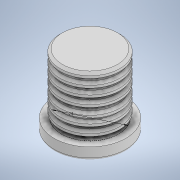
# Autodesk Inventor part: dop_teava_30_ext_24_int
Saved by Autodesk Inventor 2022.6 (Build 266554000, 554)
## iProperties
Created: 2026-07-30
Part Number: dop_teava_30_ext_24_int
Material: Generic
Document SubType Name: Modeling
Designer: Dragos Macovei
Density: 1 g/cm^3
Appearance: Default
Author: Dragos Macovei
Autodesk Inventor part; units mm, degrees
ref_plane "YZ Plane" through (0, 0, 0) normal (1, 0, 0) x (0, 1, 0)
ref_plane "XZ Plane" through (0, 0, 0) normal (0, 1, 0) x (-1, 0, 0)
ref_plane "XY Plane" through (0, 0, 0) normal (0, 0, 1) x (1, 0, 0)
sketch "Sketch1" plane through (0, 0, 0) normal (0, 1, 0) x (-1, 0, 0)
  circle A0 centre (0, 0) radius 15
  dimension "d0" = 30
  constraints: 1 centre point, 1 coincident
  measures "d0" diameter of A0
extrude "Extrusion1" add sketch "Sketch1" along normal blind 5
sketch "Sketch2" plane through (0, 5, 0) normal (0, 1, 0) x (1, 0, 0)
  circle A0 centre (0, 0) radius 7
  dimension "d3" = 14
  constraints: 1 centre point, 1 coincident
  measures "d3" diameter of A0
extrude "Extrusion2" add sketch "Sketch2" along normal blind 25
sketch "Sketch3" plane through (0, 5, 0) normal (0, 1, 0) x (1, 0, 0)
  circle A0 centre (0, 0) radius 12 construction
  dimension "d6" = 24
  constraints: 1 centre point, 1 coincident
  measures "d6" diameter of A0
sketch "Sketch4" plane through (0, 0, 0) normal (0, 0, 1) x (1, 0, 0)
  line L0 (7, 30) -> (-7, 30) projected
  line L1 (7, 30) -> (-7, 30) projected
  line L2 (0, 30) -> (0, 19.913) construction
  line L3 (7, 5) -> (7, 30) projected
  line L4 (7, 30) -> (11.5, 30)
  line L5 (12.5, 29) -> (12.5, 28)
  line L6 (12.5, 28) -> (7, 28)
  line L7 (7, 28) -> (7, 30)
  line L8 (7, 26.5) -> (11.5, 26.5)
  line L9 (12.5, 25.5) -> (12.5, 24.5)
  line L10 (12.5, 24.5) -> (7, 24.5)
  line L11 (7, 24.5) -> (7, 26.5)
  line L12 (7, 23) -> (11.5, 23)
  line L13 (12.5, 22) -> (12.5, 21)
  line L14 (12.5, 21) -> (7, 21)
  line L15 (7, 21) -> (7, 23)
  line L16 (7, 19.5) -> (11.5, 19.5)
  line L17 (12.5, 18.5) -> (12.5, 17.5)
  line L18 (12.5, 17.5) -> (7, 17.5)
  line L19 (7, 17.5) -> (7, 19.5)
  line L20 (11.5, 30) -> (12.5, 29)
  line L21 (11.5, 26.5) -> (12.5, 25.5)
  line L22 (11.5, 23) -> (12.5, 22)
  line L23 (11.5, 19.5) -> (12.5, 18.5)
  line L24 (7, 5) -> (7, 30) projected
  line L25 (7, 7) -> (12.5, 7)
  line L26 (12.5, 7) -> (12.5, 8)
  line L27 (11.5, 9) -> (7, 9)
  line L28 (7, 9) -> (7, 7)
  line L29 (10, 5) -> (10, 30) projected
  line L30 (10, 5) -> (10, 30) projected
  line L31 (11.5, 9) -> (12.5, 8)
  line L32 (7, 5) -> (7, 30) projected
  line L33 (7, 10.5) -> (12.5, 10.5)
  line L34 (12.5, 10.5) -> (12.5, 11.5)
  line L35 (11.5, 12.5) -> (7, 12.5)
  line L36 (7, 12.5) -> (7, 10.5)
  line L37 (7, 5) -> (7, 30) projected
  line L38 (7, 13.6464) -> (12.5, 13.6464)
  line L39 (12.5, 13.6464) -> (12.5, 14.6464)
  line L40 (11.5, 15.6464) -> (7, 15.6464)
  line L41 (7, 15.6464) -> (7, 13.6464)
  line L42 (12.5, 11.5) -> (11.5, 12.5)
  line L43 (12.5, 14.6464) -> (11.5, 15.6464)
  point P0 (0, 0)
  point P1 (-7, 6.5)
  point P2 (7, 6.5)
  point P3 (12.5, 30)
  point P4 (12.5, 26.5)
  point P5 (12.5, 23)
  point P6 (12.5, 19.5)
  point P7 (9.75, 28)
  point P8 (7, 17.5)
  point P9 (7, 21)
  point P10 (7, 24.5)
  point P11 (7, 28)
  point P12 (12.5, 9)
  point P13 (12.5, 12.5)
  point P14 (12.5, 15.6464)
  dimension "d8" = 5.5
  dimension "d9" = 2
  dimension "d10" = 5.5
  dimension "d11" = 2
  dimension "d12" = 5.5
  dimension "d13" = 2
  dimension "d14" = 5.5
  dimension "d15" = 2
  dimension "d16" = 1.5
  dimension "d17" = 1.5
  dimension "d18" = 1.5
  dimension "d19" = 1
  dimension "d20" = 1
  dimension "d21" = 1
  dimension "d22" = 1
  dimension "d23" = 1
  dimension "d24" = 1
  dimension "d25" = 1
  dimension "d26" = 1
  dimension "d31" = 2
  dimension "d32" = 5.5
  dimension "d40" = 1
  dimension "d41" = 1
  dimension "d42" = 5.5
  dimension "d43" = 2
  dimension "d44" = 2
  dimension "d45" = 1
  dimension "d46" = 1
  dimension "d47" = 1
  dimension "d48" = 1
  constraints: 72 end point, 19 point on line, 14 parallel, 7 horizontal, 7 perpendicular, 2 midpoint, 1 vertical, 6 other
  measures "d8" distance of L5.end L6.end
  measures "d9" distance of point (12.5, 30) L5.end
  measures "d10" distance of L9.end L10.end
  measures "d11" distance of point (12.5, 26.5) L9.end
  measures "d12" distance of L13.end L14.end
  measures "d13" distance of point (12.5, 23) L13.end
  measures "d14" distance of L17.end L18.end
  measures "d15" distance of point (12.5, 19.5) L17.end
  measures "d16" distance from line of L8 point (9.75, 28)
  measures "d17" distance between parallel lines of L12 L10
  measures "d18" distance between parallel lines of L16 L14
  measures "d19" distance of L4.end point (12.5, 30)
  measures "d20" distance of L5.start point (12.5, 30)
  measures "d21" distance of L8.end point (12.5, 26.5)
  measures "d22" distance of L9.start point (12.5, 26.5)
  measures "d23" distance of L12.end point (12.5, 23)
  measures "d24" distance of L13.start point (12.5, 23)
  measures "d25" distance of L16.end point (12.5, 19.5)
  measures "d26" distance of L17.start point (12.5, 19.5)
  measures "d31" distance of L25.end point (12.5, 9)
  measures "d32" distance of L25.start L25.end
  measures "d40" distance of L27.start point (12.5, 9)
  measures "d41" distance of L26.end point (12.5, 9)
  measures "d42" distance of L33.start L33.end
  measures "d43" distance of L33.end point (12.5, 12.5)
  measures "d44" distance of L38.end point (12.5, 15.646)
  measures "d45" distance of L34.end point (12.5, 12.5)
  measures "d46" distance of L35.start point (12.5, 12.5)
  measures "d47" distance of L39.end point (12.5, 15.646)
  measures "d48" distance of L40.start point (12.5, 15.646)
revolve "Revolution1" add sketch "Sketch4" angle 360 about axis through (0, 30, 0) along (0, -1, 0) contours L3 L27 L29 L25 | L29 L27 L31 L26 L25 | L3 L35 L29 L33 | L29 L35 L42 L34 L33 | L3 L40 L29 L38 | L29 L40 L43 L39 L38 | L3 L16 L29 L18 | L29 L16 L23 L17 L18 | L3 L12 L29 L14 | L29 L12 L22 L13 L14 | L3 L8 L29 L10 | L29 L8 L21 L9 L10 | L3 L4 L29 L6 | L29 L4 L20 L5 L6
fillet "Fillet3" radius 20 6 edges at (-7, 26.5, 0) (-7, 23, 0) (-7, 19.5, 0) (-7, 15.6464, 0) (-7, 12.5, 0) (-7, 9, 0)
fillet "Fillet4" radius 1 1 edges at (15, 0, 0)
fillet "Fillet5" radius 7 1 edges at (-7, 5, 0)
equation "\"d10\" = d8"
equation "\"d12\" = d8"
equation "\"d14\" = d8"
equation "\"d17\" = d16"
equation "\"d18\" = d17"
equation "\"d20\" = d19"
equation "\"d21\" = d19"
equation "\"d22\" = d21"
equation "\"d23\" = d19"
equation "\"d24\" = d23"
equation "\"d25\" = d19"
equation "\"d26\" = d25"
equation "\"d32\" = d14"
equation "\"d40\" = d36"
equation "\"d41\" = d40"
equation "\"d42\" = d32"
equation "\"d43\" = d11"
equation "\"d44\" = d43"
equation "\"d46\" = d45"
equation "\"d47\" = d45"
equation "\"d48\" = d47"
equation "\"d36\" = 1"
body "Solid1"
